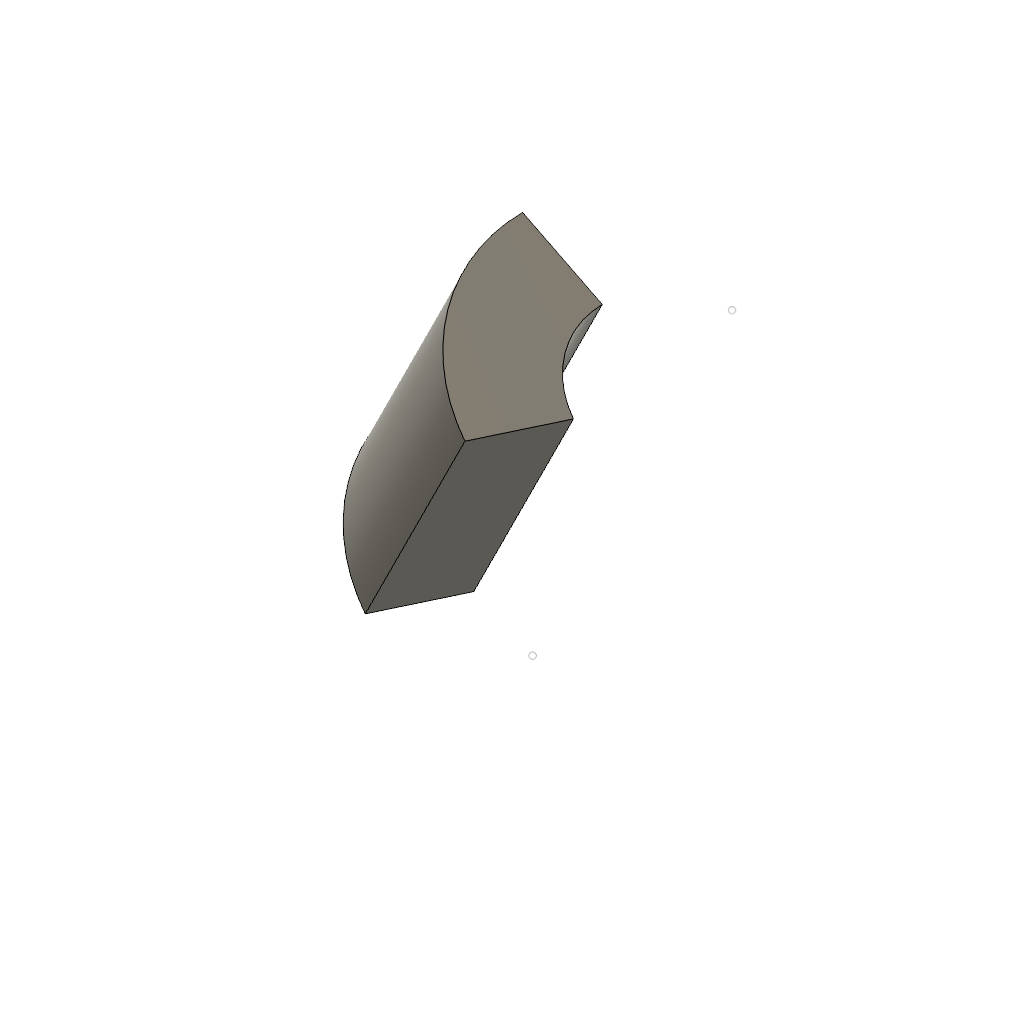
custom_two_points (Autodesk Fusion 360 design; units mm, degrees)
part number: 2026-10-20-23-01-26-885
Autodesk Fusion 360 part; units mm, degrees
sketch "AxisSupportSketch" plane through (0, 0, 0) normal (0, 0, 1) x (1, 0, 0)
  point P0 (10, -10)
  point P1 (27.8885, 25.7771)
sketch "AxisProbeProfile" plane through (0, 0, 0) normal (0, 0, 1) x (1, 0, 0)
  line L0 (7.3167, 2.522) -> (16.261, 20.4105)
  line L1 (16.261, 20.4105) -> (9.1056, 23.9882)
  line L2 (9.1056, 23.9882) -> (0.1613, 6.0997)
  line L3 (0.1613, 6.0997) -> (7.3167, 2.522)
revolve "ProbeAxisRevolve" add sketch "AxisProbeProfile" angle 73 about axis through (6.4223, -17.1554, 0) along (0.447214, 0.894427, 0)
